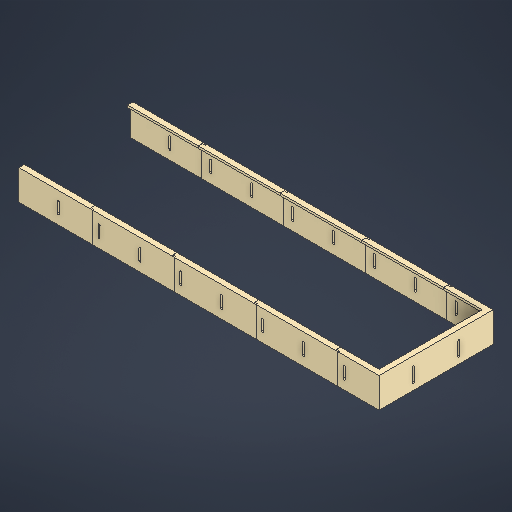
# Autodesk Inventor part: Marco_exterior_v0
Saved by Autodesk Inventor 2027 (Build 310192060, 192F)
## iProperties
Created: 2026-10-13
Part Number: Marco_exterior_v0
Material: Generic
Document SubType Name: Modeling
Designer: Pablo
Density: 1 g/cm^3
Appearance: Default
Author: Pablo
Autodesk Inventor part; units mm, degrees
ref_plane "YZ Plane" through (0, 0, 0) normal (1, 0, 0) x (0, 1, 0)
ref_plane "XZ Plane" through (0, 0, 0) normal (0, 1, 0) x (-1, 0, 0)
ref_plane "XY Plane" through (0, 0, 0) normal (0, 0, 1) x (1, 0, 0)
sketch "Sketch1" plane through (0, 0, 0) normal (1, 0, 0) x (0, 1, 0)
  line L0 (0, 0) -> (55, 0)
  line L1 (55, 0) -> (55, -10)
  line L2 (55, -10) -> (51, -10)
  line L3 (51, -10) -> (51, -4)
  line L4 (51, -4) -> (0, -4)
  line L5 (0, -4) -> (0, 0)
  dimension "d0" = 4
  dimension "d1" = 4
  dimension "d2" = 10
  dimension "d3" = 55
  constraints: 12 end point, 5 perpendicular, 1 horizontal
  measures "d0" distance of L1.end L2.end
  measures "d1" distance between parallel lines of L0 L4
  measures "d2" distance of L0.end L1.end
  measures "d3" distance of L0.start L0.end
extrude "Extrusion1" add sketch "Sketch1" along normal blind 660.5
sketch "Sketch2" plane through (0, 0, 0) normal (0, 0, 1) x (1, 0, 0)
  line L0 (0, 55) -> (0, 0) construction
  line L1 (0, 27.5) -> (723.5223, 27.5)
  line L2 (71.75, 17.5) -> (71.75, 37.5) construction
  line L3 (70, 17.5) -> (70, 37.5)
  line L4 (73.5, 37.5) -> (73.5, 17.5)
  arc A0 (70, 17.5) -> (73.5, 17.5) centre (71.75, 17.5) ccw
  arc A1 (73.5, 37.5) -> (70, 37.5) centre (71.75, 37.5) ccw
  arc A2 (148.5, 37.5) -> (145, 37.5) centre (146.75, 37.5) ccw
  line L5 (145, 17.5) -> (145, 37.5)
  line L6 (148.5, 37.5) -> (148.5, 17.5)
  arc A3 (145, 17.5) -> (148.5, 17.5) centre (146.75, 17.5) ccw
  arc A4 (223.5, 37.5) -> (220, 37.5) centre (221.75, 37.5) ccw
  line L7 (220, 17.5) -> (220, 37.5)
  line L8 (223.5, 37.5) -> (223.5, 17.5)
  arc A5 (220, 17.5) -> (223.5, 17.5) centre (221.75, 17.5) ccw
  arc A6 (298.5, 37.5) -> (295, 37.5) centre (296.75, 37.5) ccw
  line L9 (295, 17.5) -> (295, 37.5)
  line L10 (298.5, 37.5) -> (298.5, 17.5)
  arc A7 (295, 17.5) -> (298.5, 17.5) centre (296.75, 17.5) ccw
  arc A8 (373.5, 37.5) -> (370, 37.5) centre (371.75, 37.5) ccw
  line L11 (370, 17.5) -> (370, 37.5)
  line L12 (373.5, 37.5) -> (373.5, 17.5)
  arc A9 (370, 17.5) -> (373.5, 17.5) centre (371.75, 17.5) ccw
  arc A10 (448.5, 37.5) -> (445, 37.5) centre (446.75, 37.5) ccw
  line L13 (445, 17.5) -> (445, 37.5)
  line L14 (448.5, 37.5) -> (448.5, 17.5)
  arc A11 (445, 17.5) -> (448.5, 17.5) centre (446.75, 17.5) ccw
  arc A12 (523.5, 37.5) -> (520, 37.5) centre (521.75, 37.5) ccw
  line L15 (520, 17.5) -> (520, 37.5)
  line L16 (523.5, 37.5) -> (523.5, 17.5)
  arc A13 (520, 17.5) -> (523.5, 17.5) centre (521.75, 17.5) ccw
  arc A14 (598.5, 37.5) -> (595, 37.5) centre (596.75, 37.5) ccw
  line L17 (595, 17.5) -> (595, 37.5)
  line L18 (598.5, 37.5) -> (598.5, 17.5)
  arc A15 (595, 17.5) -> (598.5, 17.5) centre (596.75, 17.5) ccw
  point P0 (71.75, 27.5)
  dimension "d6" = 3.5
  dimension "d7" = 20
  dimension "d8" = 70
  dimension "d11" = 75
  constraints: 38 end point, 32 point on circle, 16 centre point, 4 tangent, 2 horizontal, 2 midpoint, 1 parallel, 1 perpendicular, 1 point on line, 70 other
  measures "d6" distance between parallel lines of L3 L4
  measures "d7" distance of L4.start L4.end
  measures "d8" distance between parallel lines of L0 L3
  measures "d11" distance of L2.end A2.centre
extrude "Extrusion2" cut sketch "Sketch2" against normal through all
sketch "Sketch3" plane through (0, 0, -4) normal (0, 0, -1) x (-1, 0, 0)
  line L0 (-660.5, 51) -> (-660.5, 55) projected
  line L1 (-660.5, 0) -> (-660.5, 55)
  line L2 (-660.5, 55) -> (-650.5, 55)
  line L3 (-650.5, 55) -> (-650.5, 50)
  line L4 (-650.5, 50) -> (-655.5, 50)
  line L5 (-655.5, 50) -> (-655.5, 0)
  line L6 (-655.5, 0) -> (-660.5, 0)
  point P0 (0, 0)
  dimension "d18" = 5
  dimension "d19" = 5
  dimension "d20" = 10
  constraints: 12 end point, 5 perpendicular, 1 vertical
  measures "d18" distance of L2.end L3.end
  measures "d19" distance between parallel lines of L1 L5
  measures "d20" distance between parallel lines of L0 L3
extrude "Extrusion3" add sketch "Sketch3" along normal blind 100.5
sketch "Sketch4" plane through (655.5, 0, -4) normal (-1, 0, 0) x (0, 0, 1)
  line L0 (0, 50) -> (0, 0) construction
  line L1 (0, 25) -> (-95.9464, 25)
  line L2 (-58.8, 37.5) -> (-58.8, 12.5) construction
  line L3 (-60.3, 37.5) -> (-60.3, 12.5)
  line L4 (-57.3, 12.5) -> (-57.3, 37.5)
  arc A0 (-57.3, 37.5) -> (-60.3, 37.5) centre (-58.8, 37.5) ccw
  arc A1 (-60.3, 12.5) -> (-57.3, 12.5) centre (-58.8, 12.5) ccw
  point P0 (4, 0)
  point P1 (-58.8, 25)
  dimension "d23" = 3
  dimension "d24" = 25
  dimension "d25" = 57.3
  constraints: 10 end point, 4 point on circle, 4 tangent, 2 centre point, 2 midpoint, 1 horizontal, 1 parallel, 1 perpendicular, 1 point on line
  measures "d23" distance between parallel lines of L3 L4
  measures "d24" distance of L3.start L3.end
  measures "d25" distance between parallel lines of L0 L4
extrude "Extrusion4" cut sketch "Sketch4" against normal through all
mirror "Mirror2" about plane through (655.5, 27.5, -104.5) normal (0, 0, -1)
sketch "Sketch5" plane through (0, 0, 0) normal (0, -1, 0) x (1, 0, 0)
  line L0 (584.9, -219) -> (585, -219)
  line L1 (0, -205) -> (650.5, -205) construction
  line L2 (0, -209) -> (660.5, -209) construction
  line L3 (0, -199) -> (650.5, -199) construction
  line L4 (0, -4) -> (655.5, -4) construction
  line L5 (0, 0) -> (660.5, 0) construction
  line L6 (0, -10) -> (650.5, -10) construction
  line L7 (655.5, -4) -> (655.5, -205) construction
  line L8 (655.5, -104.5) -> (-22.4227, -104.5)
  line L9 (585, -219) -> (585, -206.4)
  line L10 (0, -205) -> (655.5, -205) construction
  line L11 (579.9, -189) -> (579.8, -189)
  line L12 (579.8, -189) -> (579.8, -205)
  line L13 (579.9, -206.4) -> (579.9, -189)
  line L14 (579.8, -205) -> (579.8, -206.5)
  line L15 (584.9, -219) -> (584.9, -206.5)
  line L16 (579.8, -206.5) -> (584.9, -206.5)
  line L17 (585, -206.4) -> (579.9, -206.4)
  line L18 (435, -206.4) -> (429.9, -206.4)
  line L19 (429.8, -205) -> (429.8, -206.5)
  line L20 (429.8, -206.5) -> (434.9, -206.5)
  line L21 (429.9, -189) -> (429.8, -189)
  line L22 (429.8, -189) -> (429.8, -205)
  line L23 (429.9, -206.4) -> (429.9, -189)
  line L24 (434.9, -219) -> (435, -219)
  line L25 (435, -219) -> (435, -206.4)
  line L26 (434.9, -219) -> (434.9, -206.5)
  line L27 (285, -206.4) -> (279.9, -206.4)
  line L28 (279.8, -205) -> (279.8, -206.5)
  line L29 (279.8, -206.5) -> (284.9, -206.5)
  line L30 (279.9, -189) -> (279.8, -189)
  line L31 (279.8, -189) -> (279.8, -205)
  line L32 (279.9, -206.4) -> (279.9, -189)
  line L33 (284.9, -219) -> (285, -219)
  line L34 (285, -219) -> (285, -206.4)
  line L35 (284.9, -219) -> (284.9, -206.5)
  line L36 (135, -206.4) -> (129.9, -206.4)
  line L37 (129.8, -205) -> (129.8, -206.5)
  line L38 (129.8, -206.5) -> (134.9, -206.5)
  line L39 (129.9, -189) -> (129.8, -189)
  line L40 (129.8, -189) -> (129.8, -205)
  line L41 (129.9, -206.4) -> (129.9, -189)
  line L42 (134.9, -219) -> (135, -219)
  line L43 (135, -219) -> (135, -206.4)
  line L44 (134.9, -219) -> (134.9, -206.5)
  line L45 (584.9, 10) -> (585, 10)
  line L46 (585, 10) -> (585, -2.6)
  line L47 (579.9, -20) -> (579.8, -20)
  line L48 (579.8, -20) -> (579.8, -4)
  line L49 (579.9, -2.6) -> (579.9, -20)
  line L50 (579.8, -4) -> (579.8, -2.5)
  line L51 (584.9, 10) -> (584.9, -2.5)
  line L52 (579.8, -2.5) -> (584.9, -2.5)
  line L53 (585, -2.6) -> (579.9, -2.6)
  line L54 (435, -2.6) -> (429.9, -2.6)
  line L55 (429.8, -4) -> (429.8, -2.5)
  line L56 (429.8, -2.5) -> (434.9, -2.5)
  line L57 (429.9, -20) -> (429.8, -20)
  line L58 (429.8, -20) -> (429.8, -4)
  line L59 (429.9, -2.6) -> (429.9, -20)
  line L60 (434.9, 10) -> (435, 10)
  line L61 (435, 10) -> (435, -2.6)
  line L62 (434.9, 10) -> (434.9, -2.5)
  line L63 (285, -2.6) -> (279.9, -2.6)
  line L64 (279.8, -4) -> (279.8, -2.5)
  line L65 (279.8, -2.5) -> (284.9, -2.5)
  line L66 (279.9, -20) -> (279.8, -20)
  line L67 (279.8, -20) -> (279.8, -4)
  line L68 (279.9, -2.6) -> (279.9, -20)
  line L69 (284.9, 10) -> (285, 10)
  line L70 (285, 10) -> (285, -2.6)
  line L71 (284.9, 10) -> (284.9, -2.5)
  line L72 (135, -2.6) -> (129.9, -2.6)
  line L73 (129.8, -4) -> (129.8, -2.5)
  line L74 (129.8, -2.5) -> (134.9, -2.5)
  line L75 (129.9, -20) -> (129.8, -20)
  line L76 (129.8, -20) -> (129.8, -4)
  line L77 (129.9, -2.6) -> (129.9, -20)
  line L78 (134.9, 10) -> (135, 10)
  line L79 (135, 10) -> (135, -2.6)
  line L80 (134.9, 10) -> (134.9, -2.5)
  point P0 (595, -205)
  point P1 (595, -4)
  dimension "d29" = 0.1
  dimension "d30" = 5
  dimension "d31" = 0.1
  dimension "d32" = 0.1
  dimension "d33" = 2.5
  dimension "d36" = 10
  dimension "d37" = 10
  dimension "d38" = 10
  dimension "d41" = 150
  constraints: 146 end point, 37 symmetric about line, 5 horizontal, 5 perpendicular, 1 midpoint, 1 point on line, 54 other
  measures "d29" distance between parallel lines of L17 L16
  measures "d30" distance between parallel lines of L13 L15
  measures "d31" distance between parallel lines of L9 L15
  measures "d32" distance between parallel lines of L12 L13
  measures "d33" distance between parallel lines of L2 L16
  measures "d36" distance from line of L2 L0.start
  measures "d37" distance from line of L3 L11.start
  measures "d38" horizontal distance of point (595, -205) L9.end
  measures "d41" distance of L13.start L18.end
extrude "Extrusion5" cut sketch "Sketch5" against normal through all
body "Solid1"
